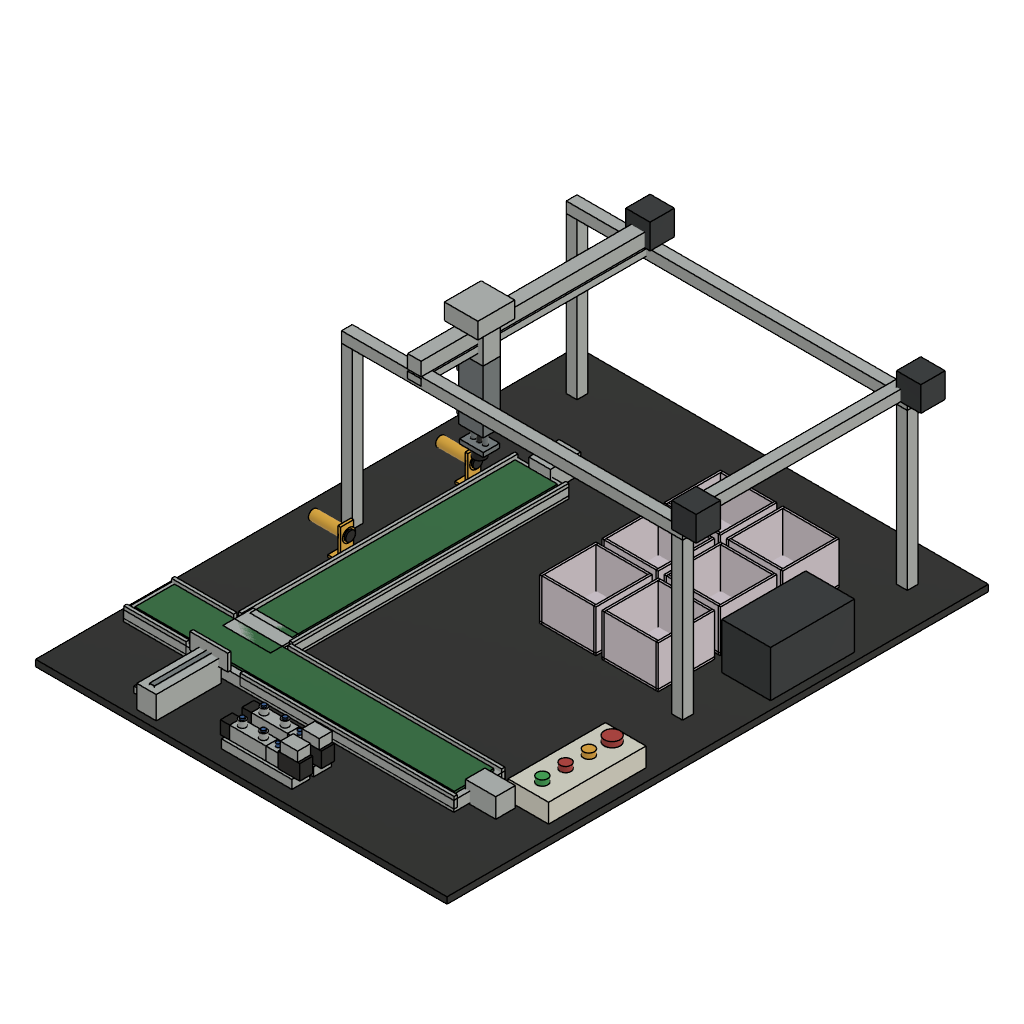
production_twin_v4 (Autodesk Fusion 360 design; units mm, degrees)
Autodesk Fusion 360 part; units mm, degrees
(part 1 of 2)
sketch "base board footprint" plane through (0, 0, 0) normal (0, 0, 1) x (1, 0, 0) in component "base board"
  line L0 (-380, -500) -> (380, -500)
  line L1 (380, -500) -> (380, 500)
  line L2 (380, 500) -> (-380, 500)
  line L3 (-380, 500) -> (-380, -500)
extrude "Extrude1" add sketch "base board footprint" along normal blind 12 makes body 1 in component "base board"
sketch "long conveyor chassis footprint" plane through (0, 0, 0) normal (0, 0, 1) x (1, 0, 0) in component "long conveyor chassis"
  line L0 (-50, -255) -> (50, -255)
  line L1 (50, -255) -> (50, 255)
  line L2 (50, 255) -> (-50, 255)
  line L3 (-50, 255) -> (-50, -255)
extrude "Extrude1'" add sketch "long conveyor chassis footprint" along normal blind 19 separate body makes body 2 in component "long conveyor chassis"
sketch "long green belt footprint" plane through (0, 0, 0) normal (0, 0, 1) x (1, 0, 0) in component "long green belt"
  line L0 (-39, -245) -> (39, -245)
  line L1 (39, -245) -> (39, 245)
  line L2 (39, 245) -> (-39, 245)
  line L3 (-39, 245) -> (-39, -245)
extrude "Extrude1''" add sketch "long green belt footprint" along normal blind 4 separate body makes body 3 in component "long green belt"
sketch "front conveyor chassis footprint" plane through (0, 0, 0) normal (0, 0, 1) x (1, 0, 0) in component "front conveyor chassis"
  line L0 (-305, -47.5) -> (305, -47.5)
  line L1 (305, -47.5) -> (305, 47.5)
  line L2 (305, 47.5) -> (-305, 47.5)
  line L3 (-305, 47.5) -> (-305, -47.5)
extrude "Extrude1'''" add sketch "front conveyor chassis footprint" along normal blind 19 separate body makes body 4 in component "front conveyor chassis"
sketch "front green belt footprint" plane through (0, 0, 0) normal (0, 0, 1) x (1, 0, 0) in component "front green belt"
  line L0 (-295, -36.5) -> (295, -36.5)
  line L1 (295, -36.5) -> (295, 36.5)
  line L2 (295, 36.5) -> (-295, 36.5)
  line L3 (-295, 36.5) -> (-295, -36.5)
extrude "Extrude1''''" add sketch "front green belt footprint" along normal blind 4 separate body makes body 5 in component "front green belt"
sketch "long conveyor side rail -1 footprint" plane through (0, 0, 0) normal (0, 0, 1) x (1, 0, 0) in component "long conveyor side rail -1"
  line L0 (-3, -255) -> (3, -255)
  line L1 (3, -255) -> (3, 255)
  line L2 (3, 255) -> (-3, 255)
  line L3 (-3, 255) -> (-3, -255)
extrude "Extrude1'''''" add sketch "long conveyor side rail -1 footprint" along normal blind 20 separate body makes body 6 in component "long conveyor side rail -1"
sketch "front conveyor side rail -1 left footprint" plane through (0, 0, 0) normal (0, 0, 1) x (1, 0, 0) in component "front conveyor side rail -1 left"
  line L0 (-57.5, -3) -> (57.5, -3)
  line L1 (57.5, -3) -> (57.5, 3)
  line L2 (57.5, 3) -> (-57.5, 3)
  line L3 (-57.5, 3) -> (-57.5, -3)
extrude "Extrude1''''''" add sketch "front conveyor side rail -1 left footprint" along normal blind 20 separate body makes body 7 in component "front conveyor side rail -1 left"
sketch "front conveyor side rail -1 right footprint" plane through (0, 0, 0) normal (0, 0, 1) x (1, 0, 0) in component "front conveyor side rail -1 right"
  line L0 (-197.5, -3) -> (197.5, -3)
  line L1 (197.5, -3) -> (197.5, 3)
  line L2 (197.5, 3) -> (-197.5, 3)
  line L3 (-197.5, 3) -> (-197.5, -3)
extrude "Extrude1'''''''" add sketch "front conveyor side rail -1 right footprint" along normal blind 20 separate body makes body 8 in component "front conveyor side rail -1 right"
sketch "long conveyor side rail 1 footprint" plane through (0, 0, 0) normal (0, 0, 1) x (1, 0, 0) in component "long conveyor side rail 1"
  line L0 (-3, -255) -> (3, -255)
  line L1 (3, -255) -> (3, 255)
  line L2 (3, 255) -> (-3, 255)
  line L3 (-3, 255) -> (-3, -255)
extrude "Extrude1''''''''" add sketch "long conveyor side rail 1 footprint" along normal blind 20 separate body makes body 9 in component "long conveyor side rail 1"
sketch "front conveyor side rail 1 left footprint" plane through (0, 0, 0) normal (0, 0, 1) x (1, 0, 0) in component "front conveyor side rail 1 left"
  line L0 (-57.5, -3) -> (57.5, -3)
  line L1 (57.5, -3) -> (57.5, 3)
  line L2 (57.5, 3) -> (-57.5, 3)
  line L3 (-57.5, 3) -> (-57.5, -3)
extrude "Extrude1'''''''''" add sketch "front conveyor side rail 1 left footprint" along normal blind 20 separate body makes body 10 in component "front conveyor side rail 1 left"
sketch "front conveyor side rail 1 right footprint" plane through (0, 0, 0) normal (0, 0, 1) x (1, 0, 0) in component "front conveyor side rail 1 right"
  line L0 (-197.5, -3) -> (197.5, -3)
  line L1 (197.5, -3) -> (197.5, 3)
  line L2 (197.5, 3) -> (-197.5, 3)
  line L3 (-197.5, 3) -> (-197.5, -3)
extrude "Extrude1''''''''''" add sketch "front conveyor side rail 1 right footprint" along normal blind 20 separate body makes body 11 in component "front conveyor side rail 1 right"
sketch "Sketch1" plane through (0, 0, 0) normal (0, 0, 1) x (1, 0, 0) in component "front conveyor roller -330"
  circle A0 centre (0, 0) radius 12
extrude "Extrude1'''''''''''" add sketch "Sketch1" along normal blind 75 separate body makes body 12 in component "front conveyor roller -330"
sketch "Sketch1 (2)" plane through (0, 0, 0) normal (0, 0, 1) x (1, 0, 0) in component "front conveyor roller 250"
  circle A0 centre (0, 0) radius 12
extrude "Extrude1''''''''''''" add sketch "Sketch1 (2)" along normal blind 75 separate body makes body 13 in component "front conveyor roller 250"
sketch "Sketch1 (3)" plane through (0, 0, 0) normal (0, 0, 1) x (1, 0, 0) in component "long conveyor roller -265"
  circle A0 centre (0, 0) radius 12
extrude "Extrude1'''''''''''''" add sketch "Sketch1 (3)" along normal blind 78 separate body makes body 14 in component "long conveyor roller -265"
sketch "Sketch1 (4)" plane through (0, 0, 0) normal (0, 0, 1) x (1, 0, 0) in component "long conveyor roller 225"
  circle A0 centre (0, 0) radius 12
extrude "Extrude1''''''''''''''" add sketch "Sketch1 (4)" along normal blind 78 separate body makes body 15 in component "long conveyor roller 225"
sketch "front conveyor DC motor footprint" plane through (0, 0, 0) normal (0, 0, 1) x (1, 0, 0) in component "front conveyor DC motor"
  line L0 (-28, -18) -> (28, -18)
  line L1 (28, -18) -> (28, 18)
  line L2 (28, 18) -> (-28, 18)
  line L3 (-28, 18) -> (-28, -18)
extrude "Extrude1'''''''''''''''" add sketch "front conveyor DC motor footprint" along normal blind 36 separate body makes body 16 in component "front conveyor DC motor"
sketch "long conveyor DC motor footprint" plane through (0, 0, 0) normal (0, 0, 1) x (1, 0, 0) in component "long conveyor DC motor"
  line L0 (-20, -28) -> (20, -28)
  line L1 (20, -28) -> (20, 28)
  line L2 (20, 28) -> (-20, 28)
  line L3 (-20, 28) -> (-20, -28)
extrude "Extrude1''''''''''''''''" add sketch "long conveyor DC motor footprint" along normal blind 36 separate body makes body 17 in component "long conveyor DC motor"
sketch "L transfer guide footprint" plane through (0, 0, 0) normal (0, 0, 1) x (1, 0, 0) in component "L transfer guide"
  line L0 (-44, -28) -> (44, -28)
  line L1 (44, -28) -> (44, 28)
  line L2 (44, 28) -> (-44, 28)
  line L3 (-44, 28) -> (-44, -28)
extrude "Extrude1'''''''''''''''''" add sketch "L transfer guide footprint" along normal blind 4 separate body makes body 18 in component "L transfer guide"
sketch "gantry post left front footprint" plane through (0, 0, 0) normal (0, 0, 1) x (1, 0, 0) in component "gantry post left front"
  line L0 (-10, -10) -> (10, -10)
  line L1 (10, -10) -> (10, 10)
  line L2 (10, 10) -> (-10, 10)
  line L3 (-10, 10) -> (-10, -10)
extrude "Extrude1''''''''''''''''''" add sketch "gantry post left front footprint" along normal blind 288 separate body makes body 19 in component "gantry post left front"
sketch "gantry post left rear footprint" plane through (0, 0, 0) normal (0, 0, 1) x (1, 0, 0) in component "gantry post left rear"
  line L0 (-10, -10) -> (10, -10)
  line L1 (10, -10) -> (10, 10)
  line L2 (10, 10) -> (-10, 10)
  line L3 (-10, 10) -> (-10, -10)
extrude "Extrude1'''''''''''''''''''" add sketch "gantry post left rear footprint" along normal blind 288 separate body makes body 20 in component "gantry post left rear"
sketch "gantry post right front footprint" plane through (0, 0, 0) normal (0, 0, 1) x (1, 0, 0) in component "gantry post right front"
  line L0 (-10, -10) -> (10, -10)
  line L1 (10, -10) -> (10, 10)
  line L2 (10, 10) -> (-10, 10)
  line L3 (-10, 10) -> (-10, -10)
extrude "Extrude1''''''''''''''''''''" add sketch "gantry post right front footprint" along normal blind 288 separate body makes body 21 in component "gantry post right front"
sketch "gantry post right rear footprint" plane through (0, 0, 0) normal (0, 0, 1) x (1, 0, 0) in component "gantry post right rear"
  line L0 (-10, -10) -> (10, -10)
  line L1 (10, -10) -> (10, 10)
  line L2 (10, 10) -> (-10, 10)
  line L3 (-10, 10) -> (-10, -10)
extrude "Extrude1'''''''''''''''''''''" add sketch "gantry post right rear footprint" along normal blind 288 separate body makes body 22 in component "gantry post right rear"
sketch "gantry X rail front footprint" plane through (0, 0, 0) normal (0, 0, 1) x (1, 0, 0) in component "gantry X rail front"
  line L0 (-315, -10) -> (315, -10)
  line L1 (315, -10) -> (315, 10)
  line L2 (315, 10) -> (-315, 10)
  line L3 (-315, 10) -> (-315, -10)
extrude "Extrude1''''''''''''''''''''''" add sketch "gantry X rail front footprint" along normal blind 20 separate body makes body 23 in component "gantry X rail front"
sketch "gantry X rail rear footprint" plane through (0, 0, 0) normal (0, 0, 1) x (1, 0, 0) in component "gantry X rail rear"
  line L0 (-315, -10) -> (315, -10)
  line L1 (315, -10) -> (315, 10)
  line L2 (315, 10) -> (-315, 10)
  line L3 (-315, 10) -> (-315, -10)
extrude "Extrude1'''''''''''''''''''''''" add sketch "gantry X rail rear footprint" along normal blind 20 separate body makes body 24 in component "gantry X rail rear"
sketch "right Y guide footprint" plane through (0, 0, 0) normal (0, 0, 1) x (1, 0, 0) in component "right Y guide"
  line L0 (-10, -217.5) -> (10, -217.5)
  line L1 (10, -217.5) -> (10, 217.5)
  line L2 (10, 217.5) -> (-10, 217.5)
  line L3 (-10, 217.5) -> (-10, -217.5)
extrude "Extrude1''''''''''''''''''''''''" add sketch "right Y guide footprint" along normal blind 20 separate body makes body 25 in component "right Y guide"
sketch "moving Y rail footprint" plane through (0, 0, 0) normal (0, 0, 1) x (1, 0, 0) in component "moving Y rail"
  line L0 (-12.5, -217.5) -> (12.5, -217.5)
  line L1 (12.5, -217.5) -> (12.5, 217.5)
  line L2 (12.5, 217.5) -> (-12.5, 217.5)
  line L3 (-12.5, 217.5) -> (-12.5, -217.5)
extrude "Extrude1'''''''''''''''''''''''''" add sketch "moving Y rail footprint" along normal blind 25 separate body makes body 26 in component "moving Y rail"
sketch "pick carriage footprint" plane through (0, 0, 0) normal (0, 0, 1) x (1, 0, 0) in component "pick carriage"
  line L0 (-31, -34) -> (31, -34)
  line L1 (31, -34) -> (31, 34)
  line L2 (31, 34) -> (-31, 34)
  line L3 (-31, 34) -> (-31, -34)
extrude "Extrude1''''''''''''''''''''''''''" add sketch "pick carriage footprint" along normal blind 30 separate body makes body 27 in component "pick carriage"
sketch "moving Y rail lower guide footprint" plane through (0, 0, 0) normal (0, 0, 1) x (1, 0, 0) in component "moving Y rail lower guide"
  line L0 (-12.5, -217.5) -> (12.5, -217.5)
  line L1 (12.5, -217.5) -> (12.5, 217.5)
  line L2 (12.5, 217.5) -> (-12.5, 217.5)
  line L3 (-12.5, 217.5) -> (-12.5, -217.5)
extrude "Extrude1'''''''''''''''''''''''''''" add sketch "moving Y rail lower guide footprint" along normal blind 12 separate body makes body 28 in component "moving Y rail lower guide"
sketch "A2 carriage mount footprint" plane through (0, 0, 0) normal (0, 0, 1) x (1, 0, 0) in component "A2 carriage mount"
  line L0 (-22.5, -16) -> (22.5, -16)
  line L1 (22.5, -16) -> (22.5, 16)
  line L2 (22.5, 16) -> (-22.5, 16)
  line L3 (-22.5, 16) -> (-22.5, -16)
extrude "Extrude1''''''''''''''''''''''''''''" add sketch "A2 carriage mount footprint" along normal blind 55 separate body makes body 29 in component "A2 carriage mount"
sketch "A2 TN10X75-S twin rod body footprint" plane through (0, 0, 0) normal (0, 0, 1) x (1, 0, 0) in component "A2 TN10X75-S twin rod body"
  line L0 (-22.5, -16) -> (22.5, -16)
  line L1 (22.5, -16) -> (22.5, 16)
  line L2 (22.5, 16) -> (-22.5, 16)
  line L3 (-22.5, 16) -> (-22.5, -16)
extrude "Extrude1'''''''''''''''''''''''''''''" add sketch "A2 TN10X75-S twin rod body footprint" along normal blind 115 separate body makes body 30 in component "A2 TN10X75-S twin rod body"
sketch "Sketch1 (5)" plane through (0, 0, 0) normal (0, 0, 1) x (1, 0, 0) in component "A2 rod at x -191"
  circle A0 centre (0, 0) radius 4
extrude "Extrude1''''''''''''''''''''''''''''''" add sketch "Sketch1 (5)" along normal blind 99 separate body makes body 31 in component "A2 rod at x -191"
sketch "Sketch1 (6)" plane through (0, 0, 0) normal (0, 0, 1) x (1, 0, 0) in component "A2 rod at x -169"
  circle A0 centre (0, 0) radius 4
extrude "Extrude1'''''''''''''''''''''''''''''''" add sketch "Sketch1 (6)" along normal blind 99 separate body makes body 32 in component "A2 rod at x -169"
sketch "A2 rod end plate footprint" plane through (0, 0, 0) normal (0, 0, 1) x (1, 0, 0) in component "A2 rod end plate"
  line L0 (-22, -15) -> (22, -15)
  line L1 (22, -15) -> (22, 15)
  line L2 (22, 15) -> (-22, 15)
  line L3 (-22, 15) -> (-22, -15)
extrude "Extrude1''''''''''''''''''''''''''''''''" add sketch "A2 rod end plate footprint" along normal blind 8 separate body makes body 33 in component "A2 rod end plate"
sketch "Sketch1 (7)" plane through (0, 0, 0) normal (0, 0, 1) x (1, 0, 0) in component "vacuum cup"
  circle A0 centre (0, 0) radius 11
extrude "Extrude1'''''''''''''''''''''''''''''''''" add sketch "Sketch1 (7)" along normal blind 16 separate body makes body 34 in component "vacuum cup"
sketch "Sketch1 (8)" plane through (0, 0, 0) normal (0, 0, 1) x (1, 0, 0) in component "vacuum cup stem"
  circle A0 centre (0, 0) radius 4
extrude "Extrude1''''''''''''''''''''''''''''''''''" add sketch "Sketch1 (8)" along normal blind 16 separate body makes body 35 in component "vacuum cup stem"
sketch "S3 A2 upper proximity switch (code pending) footprint" plane through (0, 0, 0) normal (0, 0, 1) x (1, 0, 0) in component "S3 A2 upper proximity switch (code pending)"
  line L0 (-4, -11) -> (4, -11)
  line L1 (4, -11) -> (4, 11)
  line L2 (4, 11) -> (-4, 11)
  line L3 (-4, 11) -> (-4, -11)
extrude "Extrude1'''''''''''''''''''''''''''''''''''" add sketch "S3 A2 upper proximity switch (code pending) footprint" along normal blind 13 separate body makes body 36 in component "S3 A2 upper proximity switch (code pending)"
sketch "S4 A2 lower proximity switch (code pending) footprint" plane through (0, 0, 0) normal (0, 0, 1) x (1, 0, 0) in component "S4 A2 lower proximity switch (code pending)"
  line L0 (-4, -11) -> (4, -11)
  line L1 (4, -11) -> (4, 11)
  line L2 (4, 11) -> (-4, 11)
  line L3 (-4, 11) -> (-4, -11)
extrude "Extrude1''''''''''''''''''''''''''''''''''''" add sketch "S4 A2 lower proximity switch (code pending) footprint" along normal blind 13 separate body makes body 37 in component "S4 A2 lower proximity switch (code pending)"
sketch "motor Y carriage footprint" plane through (0, 0, 0) normal (0, 0, 1) x (1, 0, 0) in component "motor Y carriage"
  line L0 (-22.5, -22.5) -> (22.5, -22.5)
  line L1 (22.5, -22.5) -> (22.5, 22.5)
  line L2 (22.5, 22.5) -> (-22.5, 22.5)
  line L3 (-22.5, 22.5) -> (-22.5, -22.5)
extrude "Extrude1'''''''''''''''''''''''''''''''''''''" add sketch "motor Y carriage footprint" along normal blind 46 separate body makes body 38 in component "motor Y carriage"
sketch "motor X rear footprint" plane through (0, 0, 0) normal (0, 0, 1) x (1, 0, 0) in component "motor X rear"
  line L0 (-22.5, -22.5) -> (22.5, -22.5)
  line L1 (22.5, -22.5) -> (22.5, 22.5)
  line L2 (22.5, 22.5) -> (-22.5, 22.5)
  line L3 (-22.5, 22.5) -> (-22.5, -22.5)
extrude "Extrude1''''''''''''''''''''''''''''''''''''''" add sketch "motor X rear footprint" along normal blind 46 separate body makes body 39 in component "motor X rear"
sketch "motor X front footprint" plane through (0, 0, 0) normal (0, 0, 1) x (1, 0, 0) in component "motor X front"
  line L0 (-22.5, -22.5) -> (22.5, -22.5)
  line L1 (22.5, -22.5) -> (22.5, 22.5)
  line L2 (22.5, 22.5) -> (-22.5, 22.5)
  line L3 (-22.5, 22.5) -> (-22.5, -22.5)
extrude "Extrude1'''''''''''''''''''''''''''''''''''''''" add sketch "motor X front footprint" along normal blind 46 separate body makes body 40 in component "motor X front"
sketch "bin R1C1 floor footprint" plane through (0, 0, 0) normal (0, 0, 1) x (1, 0, 0) in component "bin R1C1"
  line L0 (-52, -52) -> (52, -52)
  line L1 (52, -52) -> (52, 52)
  line L2 (52, 52) -> (-52, 52)
  line L3 (-52, 52) -> (-52, -52)
extrude "Extrude1''''''''''''''''''''''''''''''''''''''''" add sketch "bin R1C1 floor footprint" along normal blind 4 separate body makes body 41 in component "bin R1C1"
sketch "bin R1C1 side wall -1 footprint" plane through (0, 0, 0) normal (0, 0, 1) x (1, 0, 0) in component "bin R1C1"
  line L0 (-52, -52) -> (-48, -52)
  line L1 (-48, -52) -> (-48, 52)
  line L2 (-48, 52) -> (-52, 52)
  line L3 (-52, 52) -> (-52, -52)
extrude "Extrude2" add sketch "bin R1C1 side wall -1 footprint" along normal blind 78 separate body makes body 42 in component "bin R1C1"
sketch "bin R1C1 end wall -1 footprint" plane through (0, 0, 0) normal (0, 0, 1) x (1, 0, 0) in component "bin R1C1"
  line L0 (-48, -52) -> (48, -52)
  line L1 (48, -52) -> (48, -48)
  line L2 (48, -48) -> (-48, -48)
  line L3 (-48, -48) -> (-48, -52)
extrude "Extrude3" add sketch "bin R1C1 end wall -1 footprint" along normal blind 78 separate body makes body 43 in component "bin R1C1"
sketch "bin R1C1 side wall 1 footprint" plane through (0, 0, 0) normal (0, 0, 1) x (1, 0, 0) in component "bin R1C1"
  line L0 (48, -52) -> (52, -52)
  line L1 (52, -52) -> (52, 52)
  line L2 (52, 52) -> (48, 52)
  line L3 (48, 52) -> (48, -52)
extrude "Extrude4" add sketch "bin R1C1 side wall 1 footprint" along normal blind 78 separate body makes body 44 in component "bin R1C1"
sketch "bin R1C1 end wall 1 footprint" plane through (0, 0, 0) normal (0, 0, 1) x (1, 0, 0) in component "bin R1C1"
  line L0 (-48, 48) -> (48, 48)
  line L1 (48, 48) -> (48, 52)
  line L2 (48, 52) -> (-48, 52)
  line L3 (-48, 52) -> (-48, 48)
extrude "Extrude5" add sketch "bin R1C1 end wall 1 footprint" along normal blind 78 separate body makes body 45 in component "bin R1C1"
sketch "bin R1C2 floor footprint" plane through (0, 0, 0) normal (0, 0, 1) x (1, 0, 0) in component "bin R1C2"
  line L0 (-52, -52) -> (52, -52)
  line L1 (52, -52) -> (52, 52)
  line L2 (52, 52) -> (-52, 52)
  line L3 (-52, 52) -> (-52, -52)
extrude "Extrude1'''''''''''''''''''''''''''''''''''''''''" add sketch "bin R1C2 floor footprint" along normal blind 4 separate body makes body 46 in component "bin R1C2"
sketch "bin R1C2 side wall -1 footprint" plane through (0, 0, 0) normal (0, 0, 1) x (1, 0, 0) in component "bin R1C2"
  line L0 (-52, -52) -> (-48, -52)
  line L1 (-48, -52) -> (-48, 52)
  line L2 (-48, 52) -> (-52, 52)
  line L3 (-52, 52) -> (-52, -52)
extrude "Extrude2'" add sketch "bin R1C2 side wall -1 footprint" along normal blind 78 separate body makes body 47 in component "bin R1C2"
sketch "bin R1C2 end wall -1 footprint" plane through (0, 0, 0) normal (0, 0, 1) x (1, 0, 0) in component "bin R1C2"
  line L0 (-48, -52) -> (48, -52)
  line L1 (48, -52) -> (48, -48)
  line L2 (48, -48) -> (-48, -48)
  line L3 (-48, -48) -> (-48, -52)
extrude "Extrude3'" add sketch "bin R1C2 end wall -1 footprint" along normal blind 78 separate body makes body 48 in component "bin R1C2"
sketch "bin R1C2 side wall 1 footprint" plane through (0, 0, 0) normal (0, 0, 1) x (1, 0, 0) in component "bin R1C2"
  line L0 (48, -52) -> (52, -52)
  line L1 (52, -52) -> (52, 52)
  line L2 (52, 52) -> (48, 52)
  line L3 (48, 52) -> (48, -52)
extrude "Extrude4'" add sketch "bin R1C2 side wall 1 footprint" along normal blind 78 separate body makes body 49 in component "bin R1C2"
sketch "bin R1C2 end wall 1 footprint" plane through (0, 0, 0) normal (0, 0, 1) x (1, 0, 0) in component "bin R1C2"
  line L0 (-48, 48) -> (48, 48)
  line L1 (48, 48) -> (48, 52)
  line L2 (48, 52) -> (-48, 52)
  line L3 (-48, 52) -> (-48, 48)
extrude "Extrude5'" add sketch "bin R1C2 end wall 1 footprint" along normal blind 78 separate body makes body 50 in component "bin R1C2"
sketch "bin R2C1 floor footprint" plane through (0, 0, 0) normal (0, 0, 1) x (1, 0, 0) in component "bin R2C1"
  line L0 (-52, -52) -> (52, -52)
  line L1 (52, -52) -> (52, 52)
  line L2 (52, 52) -> (-52, 52)
  line L3 (-52, 52) -> (-52, -52)
extrude "Extrude1''''''''''''''''''''''''''''''''''''''''''" add sketch "bin R2C1 floor footprint" along normal blind 4 separate body makes body 51 in component "bin R2C1"
sketch "bin R2C1 side wall -1 footprint" plane through (0, 0, 0) normal (0, 0, 1) x (1, 0, 0) in component "bin R2C1"
  line L0 (-52, -52) -> (-48, -52)
  line L1 (-48, -52) -> (-48, 52)
  line L2 (-48, 52) -> (-52, 52)
  line L3 (-52, 52) -> (-52, -52)
extrude "Extrude2''" add sketch "bin R2C1 side wall -1 footprint" along normal blind 78 separate body makes body 52 in component "bin R2C1"
sketch "bin R2C1 end wall -1 footprint" plane through (0, 0, 0) normal (0, 0, 1) x (1, 0, 0) in component "bin R2C1"
  line L0 (-48, -52) -> (48, -52)
  line L1 (48, -52) -> (48, -48)
  line L2 (48, -48) -> (-48, -48)
  line L3 (-48, -48) -> (-48, -52)
extrude "Extrude3''" add sketch "bin R2C1 end wall -1 footprint" along normal blind 78 separate body makes body 53 in component "bin R2C1"
sketch "bin R2C1 side wall 1 footprint" plane through (0, 0, 0) normal (0, 0, 1) x (1, 0, 0) in component "bin R2C1"
  line L0 (48, -52) -> (52, -52)
  line L1 (52, -52) -> (52, 52)
  line L2 (52, 52) -> (48, 52)
  line L3 (48, 52) -> (48, -52)
extrude "Extrude4''" add sketch "bin R2C1 side wall 1 footprint" along normal blind 78 separate body makes body 54 in component "bin R2C1"
sketch "bin R2C1 end wall 1 footprint" plane through (0, 0, 0) normal (0, 0, 1) x (1, 0, 0) in component "bin R2C1"
  line L0 (-48, 48) -> (48, 48)
  line L1 (48, 48) -> (48, 52)
  line L2 (48, 52) -> (-48, 52)
  line L3 (-48, 52) -> (-48, 48)
extrude "Extrude5''" add sketch "bin R2C1 end wall 1 footprint" along normal blind 78 separate body makes body 55 in component "bin R2C1"
sketch "bin R2C2 floor footprint" plane through (0, 0, 0) normal (0, 0, 1) x (1, 0, 0) in component "bin R2C2"
  line L0 (-52, -52) -> (52, -52)
  line L1 (52, -52) -> (52, 52)
  line L2 (52, 52) -> (-52, 52)
  line L3 (-52, 52) -> (-52, -52)
extrude "Extrude1'''''''''''''''''''''''''''''''''''''''''''" add sketch "bin R2C2 floor footprint" along normal blind 4 separate body makes body 56 in component "bin R2C2"
sketch "bin R2C2 side wall -1 footprint" plane through (0, 0, 0) normal (0, 0, 1) x (1, 0, 0) in component "bin R2C2"
  line L0 (-52, -52) -> (-48, -52)
  line L1 (-48, -52) -> (-48, 52)
  line L2 (-48, 52) -> (-52, 52)
  line L3 (-52, 52) -> (-52, -52)
extrude "Extrude2'''" add sketch "bin R2C2 side wall -1 footprint" along normal blind 78 separate body makes body 57 in component "bin R2C2"
sketch "bin R2C2 end wall -1 footprint" plane through (0, 0, 0) normal (0, 0, 1) x (1, 0, 0) in component "bin R2C2"
  line L0 (-48, -52) -> (48, -52)
  line L1 (48, -52) -> (48, -48)
  line L2 (48, -48) -> (-48, -48)
  line L3 (-48, -48) -> (-48, -52)
extrude "Extrude3'''" add sketch "bin R2C2 end wall -1 footprint" along normal blind 78 separate body makes body 58 in component "bin R2C2"
sketch "bin R2C2 side wall 1 footprint" plane through (0, 0, 0) normal (0, 0, 1) x (1, 0, 0) in component "bin R2C2"
  line L0 (48, -52) -> (52, -52)
  line L1 (52, -52) -> (52, 52)
  line L2 (52, 52) -> (48, 52)
  line L3 (48, 52) -> (48, -52)
extrude "Extrude4'''" add sketch "bin R2C2 side wall 1 footprint" along normal blind 78 separate body makes body 59 in component "bin R2C2"
sketch "bin R2C2 end wall 1 footprint" plane through (0, 0, 0) normal (0, 0, 1) x (1, 0, 0) in component "bin R2C2"
  line L0 (-48, 48) -> (48, 48)
  line L1 (48, 48) -> (48, 52)
  line L2 (48, 52) -> (-48, 52)
  line L3 (-48, 52) -> (-48, 48)
extrude "Extrude5'''" add sketch "bin R2C2 end wall 1 footprint" along normal blind 78 separate body makes body 60 in component "bin R2C2"
sketch "bin R3C1 floor footprint" plane through (0, 0, 0) normal (0, 0, 1) x (1, 0, 0) in component "bin R3C1"
  line L0 (-52, -52) -> (52, -52)
  line L1 (52, -52) -> (52, 52)
  line L2 (52, 52) -> (-52, 52)
  line L3 (-52, 52) -> (-52, -52)
extrude "Extrude1''''''''''''''''''''''''''''''''''''''''''''" add sketch "bin R3C1 floor footprint" along normal blind 4 separate body makes body 61 in component "bin R3C1"
sketch "bin R3C1 side wall -1 footprint" plane through (0, 0, 0) normal (0, 0, 1) x (1, 0, 0) in component "bin R3C1"
  line L0 (-52, -52) -> (-48, -52)
  line L1 (-48, -52) -> (-48, 52)
  line L2 (-48, 52) -> (-52, 52)
  line L3 (-52, 52) -> (-52, -52)
extrude "Extrude2''''" add sketch "bin R3C1 side wall -1 footprint" along normal blind 78 separate body makes body 62 in component "bin R3C1"
sketch "bin R3C1 end wall -1 footprint" plane through (0, 0, 0) normal (0, 0, 1) x (1, 0, 0) in component "bin R3C1"
  line L0 (-48, -52) -> (48, -52)
  line L1 (48, -52) -> (48, -48)
  line L2 (48, -48) -> (-48, -48)
  line L3 (-48, -48) -> (-48, -52)
extrude "Extrude3''''" add sketch "bin R3C1 end wall -1 footprint" along normal blind 78 separate body makes body 63 in component "bin R3C1"
sketch "bin R3C1 side wall 1 footprint" plane through (0, 0, 0) normal (0, 0, 1) x (1, 0, 0) in component "bin R3C1"
  line L0 (48, -52) -> (52, -52)
  line L1 (52, -52) -> (52, 52)
  line L2 (52, 52) -> (48, 52)
  line L3 (48, 52) -> (48, -52)
extrude "Extrude4''''" add sketch "bin R3C1 side wall 1 footprint" along normal blind 78 separate body makes body 64 in component "bin R3C1"
sketch "bin R3C1 end wall 1 footprint" plane through (0, 0, 0) normal (0, 0, 1) x (1, 0, 0) in component "bin R3C1"
  line L0 (-48, 48) -> (48, 48)
  line L1 (48, 48) -> (48, 52)
  line L2 (48, 52) -> (-48, 52)
  line L3 (-48, 52) -> (-48, 48)
extrude "Extrude5''''" add sketch "bin R3C1 end wall 1 footprint" along normal blind 78 separate body makes body 65 in component "bin R3C1"
sketch "bin R3C2 floor footprint" plane through (0, 0, 0) normal (0, 0, 1) x (1, 0, 0) in component "bin R3C2"
  line L0 (-52, -52) -> (52, -52)
  line L1 (52, -52) -> (52, 52)
  line L2 (52, 52) -> (-52, 52)
  line L3 (-52, 52) -> (-52, -52)
extrude "Extrude1'''''''''''''''''''''''''''''''''''''''''''''" add sketch "bin R3C2 floor footprint" along normal blind 4 separate body makes body 66 in component "bin R3C2"
sketch "bin R3C2 side wall -1 footprint" plane through (0, 0, 0) normal (0, 0, 1) x (1, 0, 0) in component "bin R3C2"
  line L0 (-52, -52) -> (-48, -52)
  line L1 (-48, -52) -> (-48, 52)
  line L2 (-48, 52) -> (-52, 52)
  line L3 (-52, 52) -> (-52, -52)
extrude "Extrude2'''''" add sketch "bin R3C2 side wall -1 footprint" along normal blind 78 separate body makes body 67 in component "bin R3C2"
sketch "bin R3C2 end wall -1 footprint" plane through (0, 0, 0) normal (0, 0, 1) x (1, 0, 0) in component "bin R3C2"
  line L0 (-48, -52) -> (48, -52)
  line L1 (48, -52) -> (48, -48)
  line L2 (48, -48) -> (-48, -48)
  line L3 (-48, -48) -> (-48, -52)
extrude "Extrude3'''''" add sketch "bin R3C2 end wall -1 footprint" along normal blind 78 separate body makes body 68 in component "bin R3C2"
sketch "bin R3C2 side wall 1 footprint" plane through (0, 0, 0) normal (0, 0, 1) x (1, 0, 0) in component "bin R3C2"
  line L0 (48, -52) -> (52, -52)
  line L1 (52, -52) -> (52, 52)
  line L2 (52, 52) -> (48, 52)
  line L3 (48, 52) -> (48, -52)
extrude "Extrude4'''''" add sketch "bin R3C2 side wall 1 footprint" along normal blind 78 separate body makes body 69 in component "bin R3C2"
sketch "bin R3C2 end wall 1 footprint" plane through (0, 0, 0) normal (0, 0, 1) x (1, 0, 0) in component "bin R3C2"
  line L0 (-48, 48) -> (48, 48)
  line L1 (48, 48) -> (48, 52)
  line L2 (48, 52) -> (-48, 52)
  line L3 (-48, 52) -> (-48, 48)
extrude "Extrude5'''''" add sketch "bin R3C2 end wall 1 footprint" along normal blind 78 separate body makes body 70 in component "bin R3C2"
sketch "PS1 bracket foot footprint" plane through (0, 0, 0) normal (0, 0, 1) x (1, 0, 0) in component "PS1 bracket foot"
  line L0 (-17.5, -12) -> (17.5, -12)
  line L1 (17.5, -12) -> (17.5, 12)
  line L2 (17.5, 12) -> (-17.5, 12)
  line L3 (-17.5, 12) -> (-17.5, -12)
extrude "Extrude1''''''''''''''''''''''''''''''''''''''''''''''" add sketch "PS1 bracket foot footprint" along normal blind 4 separate body makes body 71 in component "PS1 bracket foot"
sketch "PS1 bracket upright footprint" plane through (0, 0, 0) normal (0, 0, 1) x (1, 0, 0) in component "PS1 bracket upright"
  line L0 (-2.5, -12) -> (2.5, -12)
  line L1 (2.5, -12) -> (2.5, 12)
  line L2 (2.5, 12) -> (-2.5, 12)
  line L3 (-2.5, 12) -> (-2.5, -12)
extrude "Extrude1'''''''''''''''''''''''''''''''''''''''''''''''" add sketch "PS1 bracket upright footprint" along normal blind 56 separate body makes body 72 in component "PS1 bracket upright"
sketch "Sketch1 (9)" plane through (0, 0, 0) normal (0, 0, 1) x (1, 0, 0) in component "PS1 YF-KJ E3F-DS30C4 M18 body"
  circle A0 centre (0, 0) radius 9
extrude "Extrude1''''''''''''''''''''''''''''''''''''''''''''''''" add sketch "Sketch1 (9)" along normal blind 58 separate body makes body 73 in component "PS1 YF-KJ E3F-DS30C4 M18 body"
sketch "Sketch1 (10)" plane through (0, 0, 0) normal (0, 0, 1) x (1, 0, 0) in component "PS1 locking ring"
  circle A0 centre (0, 0) radius 12
extrude "Extrude1'''''''''''''''''''''''''''''''''''''''''''''''''" add sketch "Sketch1 (10)" along normal blind 8 separate body makes body 74 in component "PS1 locking ring"
sketch "Sketch1 (11)" plane through (0, 0, 0) normal (0, 0, 1) x (1, 0, 0) in component "PS1 optical face"
  circle A0 centre (0, 0) radius 9
extrude "Extrude1''''''''''''''''''''''''''''''''''''''''''''''''''" add sketch "Sketch1 (11)" along normal blind 3 separate body makes body 75 in component "PS1 optical face"
sketch "PS2 bracket foot footprint" plane through (0, 0, 0) normal (0, 0, 1) x (1, 0, 0) in component "PS2 bracket foot"
  line L0 (-17.5, -12) -> (17.5, -12)
  line L1 (17.5, -12) -> (17.5, 12)
  line L2 (17.5, 12) -> (-17.5, 12)
  line L3 (-17.5, 12) -> (-17.5, -12)
extrude "Extrude1'''''''''''''''''''''''''''''''''''''''''''''''''''" add sketch "PS2 bracket foot footprint" along normal blind 4 separate body makes body 76 in component "PS2 bracket foot"
sketch "PS2 bracket upright footprint" plane through (0, 0, 0) normal (0, 0, 1) x (1, 0, 0) in component "PS2 bracket upright"
  line L0 (-2.5, -12) -> (2.5, -12)
  line L1 (2.5, -12) -> (2.5, 12)
  line L2 (2.5, 12) -> (-2.5, 12)
  line L3 (-2.5, 12) -> (-2.5, -12)
extrude "Extrude1''''''''''''''''''''''''''''''''''''''''''''''''''''" add sketch "PS2 bracket upright footprint" along normal blind 56 separate body makes body 77 in component "PS2 bracket upright"
sketch "Sketch1 (12)" plane through (0, 0, 0) normal (0, 0, 1) x (1, 0, 0) in component "PS2 YF-KJ E3F-DS30C4 M18 body"
  circle A0 centre (0, 0) radius 9
extrude "Extrude1'''''''''''''''''''''''''''''''''''''''''''''''''''''" add sketch "Sketch1 (12)" along normal blind 58 separate body makes body 78 in component "PS2 YF-KJ E3F-DS30C4 M18 body"
sketch "Sketch1 (13)" plane through (0, 0, 0) normal (0, 0, 1) x (1, 0, 0) in component "PS2 locking ring"
  circle A0 centre (0, 0) radius 12
extrude "Extrude1''''''''''''''''''''''''''''''''''''''''''''''''''''''" add sketch "Sketch1 (13)" along normal blind 8 separate body makes body 79 in component "PS2 locking ring"
sketch "Sketch1 (14)" plane through (0, 0, 0) normal (0, 0, 1) x (1, 0, 0) in component "PS2 optical face"
  circle A0 centre (0, 0) radius 9
extrude "Extrude1'''''''''''''''''''''''''''''''''''''''''''''''''''''''" add sketch "Sketch1 (14)" along normal blind 3 separate body makes body 80 in component "PS2 optical face"
sketch "A1 front pusher cylinder footprint" plane through (0, 0, 0) normal (0, 0, 1) x (1, 0, 0) in component "A1 front pusher cylinder"
  line L0 (-18, -60) -> (18, -60)
  line L1 (18, -60) -> (18, 60)
  line L2 (18, 60) -> (-18, 60)
  line L3 (-18, 60) -> (-18, -60)
extrude "Extrude1''''''''''''''''''''''''''''''''''''''''''''''''''''''''" add sketch "A1 front pusher cylinder footprint" along normal blind 42 separate body makes body 81 in component "A1 front pusher cylinder"
sketch "A1 pusher rod footprint" plane through (0, 0, 0) normal (0, 0, 1) x (1, 0, 0) in component "A1 pusher rod"
  line L0 (-4.5, -54) -> (4.5, -54)
  line L1 (4.5, -54) -> (4.5, 54)
  line L2 (4.5, 54) -> (-4.5, 54)
  line L3 (-4.5, 54) -> (-4.5, -54)
extrude "Extrude1'''''''''''''''''''''''''''''''''''''''''''''''''''''''''" add sketch "A1 pusher rod footprint" along normal blind 9 separate body makes body 82 in component "A1 pusher rod"
sketch "A1 pusher plate footprint" plane through (0, 0, 0) normal (0, 0, 1) x (1, 0, 0) in component "A1 pusher plate"
  line L0 (-35, -3) -> (35, -3)
  line L1 (35, -3) -> (35, 3)
  line L2 (35, 3) -> (-35, 3)
  line L3 (-35, 3) -> (-35, -3)
extrude "Extrude1''''''''''''''''''''''''''''''''''''''''''''''''''''''''''" add sketch "A1 pusher plate footprint" along normal blind 30 separate body makes body 83 in component "A1 pusher plate"
sketch "S1 A1 retracted switch (code pending) footprint" plane through (0, 0, 0) normal (0, 0, 1) x (1, 0, 0) in component "S1 A1 retracted switch (code pending)"
  line L0 (-4.5, -8) -> (4.5, -8)
  line L1 (4.5, -8) -> (4.5, 8)
  line L2 (4.5, 8) -> (-4.5, 8)
  line L3 (-4.5, 8) -> (-4.5, -8)
extrude "Extrude1'''''''''''''''''''''''''''''''''''''''''''''''''''''''''''" add sketch "S1 A1 retracted switch (code pending) footprint" along normal blind 11 separate body makes body 84 in component "S1 A1 retracted switch (code pending)"
sketch "S2 A1 extended switch (code pending) footprint" plane through (0, 0, 0) normal (0, 0, 1) x (1, 0, 0) in component "S2 A1 extended switch (code pending)"
  line L0 (-4.5, -8) -> (4.5, -8)
  line L1 (4.5, -8) -> (4.5, 8)
  line L2 (4.5, 8) -> (-4.5, 8)
  line L3 (-4.5, 8) -> (-4.5, -8)
extrude "Extrude1''''''''''''''''''''''''''''''''''''''''''''''''''''''''''''" add sketch "S2 A1 extended switch (code pending) footprint" along normal blind 11 separate body makes body 85 in component "S2 A1 extended switch (code pending)"
sketch "Y1 4V210-08 manifold footprint" plane through (0, 0, 0) normal (0, 0, 1) x (1, 0, 0) in component "Y1 4V210-08 manifold"
  line L0 (-65, -16.5) -> (65, -16.5)
  line L1 (65, -16.5) -> (65, 16.5)
  line L2 (65, 16.5) -> (-65, 16.5)
  line L3 (-65, 16.5) -> (-65, -16.5)
extrude "Extrude1'''''''''''''''''''''''''''''''''''''''''''''''''''''''''''''" add sketch "Y1 4V210-08 manifold footprint" along normal blind 16 separate body makes body 86 in component "Y1 4V210-08 manifold"
sketch "Y1 4V210-08 aluminum body footprint" plane through (0, 0, 0) normal (0, 0, 1) x (1, 0, 0) in component "Y1 4V210-08 aluminum body"
  line L0 (-33.5, -11) -> (33.5, -11)
  line L1 (33.5, -11) -> (33.5, 11)
  line L2 (33.5, 11) -> (-33.5, 11)
  line L3 (-33.5, 11) -> (-33.5, -11)
extrude "Extrude1''''''''''''''''''''''''''''''''''''''''''''''''''''''''''''''" add sketch "Y1 4V210-08 aluminum body footprint" along normal blind 24 separate body makes body 87 in component "Y1 4V210-08 aluminum body"
sketch "Y1 spring cap footprint" plane through (0, 0, 0) normal (0, 0, 1) x (1, 0, 0) in component "Y1 spring cap"
  line L0 (-8.5, -11) -> (8.5, -11)
  line L1 (8.5, -11) -> (8.5, 11)
  line L2 (8.5, 11) -> (-8.5, 11)
  line L3 (-8.5, 11) -> (-8.5, -11)
extrude "Extrude1'''''''''''''''''''''''''''''''''''''''''''''''''''''''''''''''" add sketch "Y1 spring cap footprint" along normal blind 24 separate body makes body 88 in component "Y1 spring cap"
sketch "Y1 pilot and manual override footprint" plane through (0, 0, 0) normal (0, 0, 1) x (1, 0, 0) in component "Y1 pilot and manual override"
  line L0 (-11.5, -11) -> (11.5, -11)
  line L1 (11.5, -11) -> (11.5, 11)
  line L2 (11.5, 11) -> (-11.5, 11)
  line L3 (-11.5, 11) -> (-11.5, -11)
extrude "Extrude1''''''''''''''''''''''''''''''''''''''''''''''''''''''''''''''''" add sketch "Y1 pilot and manual override footprint" along normal blind 24 separate body makes body 89 in component "Y1 pilot and manual override"
sketch "Y1 DC24V 4.8W 200mA coil footprint" plane through (0, 0, 0) normal (0, 0, 1) x (1, 0, 0) in component "Y1 DC24V 4.8W 200mA coil"
  line L0 (-20, -12) -> (20, -12)
  line L1 (20, -12) -> (20, 12)
  line L2 (20, 12) -> (-20, 12)
  line L3 (-20, 12) -> (-20, -12)
extrude "Extrude1'''''''''''''''''''''''''''''''''''''''''''''''''''''''''''''''''" add sketch "Y1 DC24V 4.8W 200mA coil footprint" along normal blind 28 separate body makes body 90 in component "Y1 DC24V 4.8W 200mA coil"
sketch "Y1 DIN plug footprint" plane through (0, 0, 0) normal (0, 0, 1) x (1, 0, 0) in component "Y1 DIN plug"
  line L0 (-16, -12) -> (16, -12)
  line L1 (16, -12) -> (16, 12)
  line L2 (16, 12) -> (-16, 12)
  line L3 (-16, 12) -> (-16, -12)
extrude "Extrude1''''''''''''''''''''''''''''''''''''''''''''''''''''''''''''''''''" add sketch "Y1 DIN plug footprint" along normal blind 18 separate body makes body 91 in component "Y1 DIN plug"
sketch "Sketch1 (15)" plane through (0, 0, 0) normal (0, 0, 1) x (1, 0, 0) in component "Y1 manual button"
  circle A0 centre (0, 0) radius 3.5
extrude "Extrude1'''''''''''''''''''''''''''''''''''''''''''''''''''''''''''''''''''" add sketch "Sketch1 (15)" along normal blind 6 separate body makes body 92 in component "Y1 manual button"
sketch "Sketch1 (16)" plane through (0, 0, 0) normal (0, 0, 1) x (1, 0, 0) in component "Y1 port A fitting"
  circle A0 centre (0, 0) radius 6.5
extrude "Extrude1''''''''''''''''''''''''''''''''''''''''''''''''''''''''''''''''''''" add sketch "Sketch1 (16)" along normal blind 11 separate body makes body 93 in component "Y1 port A fitting"
sketch "Sketch1 (17)" plane through (0, 0, 0) normal (0, 0, 1) x (1, 0, 0) in component "Y1 port A collet"
  circle A0 centre (0, 0) radius 4
extrude "Extrude1'''''''''''''''''''''''''''''''''''''''''''''''''''''''''''''''''''''" add sketch "Sketch1 (17)" along normal blind 3 separate body makes body 94 in component "Y1 port A collet"
sketch "Sketch1 (18)" plane through (0, 0, 0) normal (0, 0, 1) x (1, 0, 0) in component "Y1 port B fitting"
  circle A0 centre (0, 0) radius 6.5
extrude "Extrude1''''''''''''''''''''''''''''''''''''''''''''''''''''''''''''''''''''''" add sketch "Sketch1 (18)" along normal blind 11 separate body makes body 95 in component "Y1 port B fitting"
sketch "Sketch1 (19)" plane through (0, 0, 0) normal (0, 0, 1) x (1, 0, 0) in component "Y1 port B collet"
  circle A0 centre (0, 0) radius 4
extrude "Extrude1'''''''''''''''''''''''''''''''''''''''''''''''''''''''''''''''''''''''" add sketch "Sketch1 (19)" along normal blind 3 separate body makes body 96 in component "Y1 port B collet"
sketch "Y2 4V210-08 manifold footprint" plane through (0, 0, 0) normal (0, 0, 1) x (1, 0, 0) in component "Y2 4V210-08 manifold"
  line L0 (-65, -16.5) -> (65, -16.5)
  line L1 (65, -16.5) -> (65, 16.5)
  line L2 (65, 16.5) -> (-65, 16.5)
  line L3 (-65, 16.5) -> (-65, -16.5)
extrude "Extrude1''''''''''''''''''''''''''''''''''''''''''''''''''''''''''''''''''''''''" add sketch "Y2 4V210-08 manifold footprint" along normal blind 16 separate body makes body 97 in component "Y2 4V210-08 manifold"
sketch "Y2 4V210-08 aluminum body footprint" plane through (0, 0, 0) normal (0, 0, 1) x (1, 0, 0) in component "Y2 4V210-08 aluminum body"
  line L0 (-33.5, -11) -> (33.5, -11)
  line L1 (33.5, -11) -> (33.5, 11)
  line L2 (33.5, 11) -> (-33.5, 11)
  line L3 (-33.5, 11) -> (-33.5, -11)
extrude "Extrude1'''''''''''''''''''''''''''''''''''''''''''''''''''''''''''''''''''''''''" add sketch "Y2 4V210-08 aluminum body footprint" along normal blind 24 separate body makes body 98 in component "Y2 4V210-08 aluminum body"
sketch "Y2 spring cap footprint" plane through (0, 0, 0) normal (0, 0, 1) x (1, 0, 0) in component "Y2 spring cap"
  line L0 (-8.5, -11) -> (8.5, -11)
  line L1 (8.5, -11) -> (8.5, 11)
  line L2 (8.5, 11) -> (-8.5, 11)
  line L3 (-8.5, 11) -> (-8.5, -11)
extrude "Extrude1''''''''''''''''''''''''''''''''''''''''''''''''''''''''''''''''''''''''''" add sketch "Y2 spring cap footprint" along normal blind 24 separate body makes body 99 in component "Y2 spring cap"
sketch "Y2 pilot and manual override footprint" plane through (0, 0, 0) normal (0, 0, 1) x (1, 0, 0) in component "Y2 pilot and manual override"
  line L0 (-11.5, -11) -> (11.5, -11)
  line L1 (11.5, -11) -> (11.5, 11)
  line L2 (11.5, 11) -> (-11.5, 11)
  line L3 (-11.5, 11) -> (-11.5, -11)
extrude "Extrude1'''''''''''''''''''''''''''''''''''''''''''''''''''''''''''''''''''''''''''" add sketch "Y2 pilot and manual override footprint" along normal blind 24 separate body makes body 100 in component "Y2 pilot and manual override"
sketch "Y2 DC24V 4.8W 200mA coil footprint" plane through (0, 0, 0) normal (0, 0, 1) x (1, 0, 0) in component "Y2 DC24V 4.8W 200mA coil"
  line L0 (-20, -12) -> (20, -12)
  line L1 (20, -12) -> (20, 12)
  line L2 (20, 12) -> (-20, 12)
  line L3 (-20, 12) -> (-20, -12)
extrude "Extrude1''''''''''''''''''''''''''''''''''''''''''''''''''''''''''''''''''''''''''''" add sketch "Y2 DC24V 4.8W 200mA coil footprint" along normal blind 28 separate body makes body 101 in component "Y2 DC24V 4.8W 200mA coil"
sketch "Y2 DIN plug footprint" plane through (0, 0, 0) normal (0, 0, 1) x (1, 0, 0) in component "Y2 DIN plug"
  line L0 (-16, -12) -> (16, -12)
  line L1 (16, -12) -> (16, 12)
  line L2 (16, 12) -> (-16, 12)
  line L3 (-16, 12) -> (-16, -12)
extrude "Extrude1'''''''''''''''''''''''''''''''''''''''''''''''''''''''''''''''''''''''''''''" add sketch "Y2 DIN plug footprint" along normal blind 18 separate body makes body 102 in component "Y2 DIN plug"
sketch "Sketch1 (20)" plane through (0, 0, 0) normal (0, 0, 1) x (1, 0, 0) in component "Y2 manual button"
  circle A0 centre (0, 0) radius 3.5
extrude "Extrude1''''''''''''''''''''''''''''''''''''''''''''''''''''''''''''''''''''''''''''''" add sketch "Sketch1 (20)" along normal blind 6 separate body makes body 103 in component "Y2 manual button"
sketch "Sketch1 (21)" plane through (0, 0, 0) normal (0, 0, 1) x (1, 0, 0) in component "Y2 port A fitting"
  circle A0 centre (0, 0) radius 6.5
extrude "Extrude1'''''''''''''''''''''''''''''''''''''''''''''''''''''''''''''''''''''''''''''''" add sketch "Sketch1 (21)" along normal blind 11 separate body makes body 104 in component "Y2 port A fitting"
sketch "Sketch1 (22)" plane through (0, 0, 0) normal (0, 0, 1) x (1, 0, 0) in component "Y2 port A collet"
  circle A0 centre (0, 0) radius 4
extrude "Extrude1''''''''''''''''''''''''''''''''''''''''''''''''''''''''''''''''''''''''''''''''" add sketch "Sketch1 (22)" along normal blind 3 separate body makes body 105 in component "Y2 port A collet"
sketch "Sketch1 (23)" plane through (0, 0, 0) normal (0, 0, 1) x (1, 0, 0) in component "Y2 port B fitting"
  circle A0 centre (0, 0) radius 6.5
extrude "Extrude1'''''''''''''''''''''''''''''''''''''''''''''''''''''''''''''''''''''''''''''''''" add sketch "Sketch1 (23)" along normal blind 11 separate body makes body 106 in component "Y2 port B fitting"
sketch "Sketch1 (24)" plane through (0, 0, 0) normal (0, 0, 1) x (1, 0, 0) in component "Y2 port B collet"
  circle A0 centre (0, 0) radius 4
extrude "Extrude1''''''''''''''''''''''''''''''''''''''''''''''''''''''''''''''''''''''''''''''''''" add sketch "Sketch1 (24)" along normal blind 3 separate body makes body 107 in component "Y2 port B collet"
sketch "PLC 1214C envelope footprint" plane through (0, 0, 0) normal (0, 0, 1) x (1, 0, 0) in component "PLC 1214C envelope"
  line L0 (-45, -77.5) -> (45, -77.5)
  line L1 (45, -77.5) -> (45, 77.5)
  line L2 (45, 77.5) -> (-45, 77.5)
  line L3 (-45, 77.5) -> (-45, -77.5)
extrude "Extrude1'''''''''''''''''''''''''''''''''''''''''''''''''''''''''''''''''''''''''''''''''''" add sketch "PLC 1214C envelope footprint" along normal blind 85 separate body makes body 108 in component "PLC 1214C envelope"
sketch "button station envelope footprint" plane through (0, 0, 0) normal (0, 0, 1) x (1, 0, 0) in component "button station envelope"
  line L0 (-37.5, -90) -> (37.5, -90)
  line L1 (37.5, -90) -> (37.5, 90)
  line L2 (37.5, 90) -> (-37.5, 90)
  line L3 (-37.5, 90) -> (-37.5, -90)
extrude "Extrude1''''''''''''''''''''''''''''''''''''''''''''''''''''''''''''''''''''''''''''''''''''" add sketch "button station envelope footprint" along normal blind 35 separate body makes body 109 in component "button station envelope"
sketch "Sketch1 (25)" plane through (0, 0, 0) normal (0, 0, 1) x (1, 0, 0) in component "button EStop"
  circle A0 centre (0, 0) radius 14.5
extrude "Extrude1'''''''''''''''''''''''''''''''''''''''''''''''''''''''''''''''''''''''''''''''''''''" add sketch "Sketch1 (25)" along normal blind 10 separate body makes body 110 in component "button EStop"
sketch "Sketch1 (26)" plane through (0, 0, 0) normal (0, 0, 1) x (1, 0, 0) in component "button Reset"
  circle A0 centre (0, 0) radius 10
extrude "Extrude1''''''''''''''''''''''''''''''''''''''''''''''''''''''''''''''''''''''''''''''''''''''" add sketch "Sketch1 (26)" along normal blind 10 separate body makes body 111 in component "button Reset"
sketch "Sketch1 (27)" plane through (0, 0, 0) normal (0, 0, 1) x (1, 0, 0) in component "button Stop"
  circle A0 centre (0, 0) radius 10
extrude "Extrude1'''''''''''''''''''''''''''''''''''''''''''''''''''''''''''''''''''''''''''''''''''''''" add sketch "Sketch1 (27)" along normal blind 10 separate body makes body 112 in component "button Stop"
sketch "Sketch1 (28)" plane through (0, 0, 0) normal (0, 0, 1) x (1, 0, 0) in component "button Start"
  circle A0 centre (0, 0) radius 10
extrude "Extrude1''''''''''''''''''''''''''''''''''''''''''''''''''''''''''''''''''''''''''''''''''''''''" add sketch "Sketch1 (28)" along normal blind 10 separate body makes body 113 in component "button Start"
component "base board" placed x (1, 0, 0) y (0, 1, 0) z (0, 0, 1) at (0, 0, 0)
component "long conveyor chassis" placed x (1, 0, 0) y (0, 1, 0) z (0, 0, 1) at (-180, -20, 26)
component "long green belt" placed x (1, 0, 0) y (0, 1, 0) z (0, 0, 1) at (-180, -20, 45)
component "front conveyor chassis" placed x (1, 0, 0) y (0, 1, 0) z (0, 0, 1) at (-40, -325, 26)
component "front green belt" placed x (1, 0, 0) y (0, 1, 0) z (0, 0, 1) at (-40, -325, 45)
component "long conveyor side rail -1" placed x (1, 0, 0) y (0, 1, 0) z (0, 0, 1) at (-227, -20, 31)
component "front conveyor side rail -1 left" placed x (1, 0, 0) y (0, 1, 0) z (0, 0, 1) at (-287.5, -369, 31)
component "front conveyor side rail -1 right" placed x (1, 0, 0) y (0, 1, 0) z (0, 0, 1) at (67.5, -369, 31)
component "long conveyor side rail 1" placed x (1, 0, 0) y (0, 1, 0) z (0, 0, 1) at (-133, -20, 31)
component "front conveyor side rail 1 left" placed x (1, 0, 0) y (0, 1, 0) z (0, 0, 1) at (-287.5, -281, 31)
component "front conveyor side rail 1 right" placed x (1, 0, 0) y (0, 1, 0) z (0, 0, 1) at (67.5, -281, 31)
component "front conveyor roller -330" placed x (1, 0, 0) y (0, 0, -1) z (0, 1, 0) at (-330, -362, 29)
component "front conveyor roller 250" placed x (1, 0, 0) y (0, 0, -1) z (0, 1, 0) at (250, -362, 29)
component "long conveyor roller -265" placed x (0, 0, -1) y (0, 1, 0) z (1, 0, 0) at (-219, -265, 29)
component "long conveyor roller 225" placed x (0, 0, -1) y (0, 1, 0) z (1, 0, 0) at (-219, 225, 29)
component "front conveyor DC motor" placed x (1, 0, 0) y (0, 1, 0) z (0, 0, 1) at (285, -325, 24)
component "long conveyor DC motor" placed x (1, 0, 0) y (0, 1, 0) z (0, 0, 1) at (-180, 259, 24)
component "L transfer guide" placed x (1, 0, 0) y (0, 1, 0) z (0, 0, 1) at (-180, -282, 45)
component "gantry post left front" placed x (1, 0, 0) y (0, 1, 0) z (0, 0, 1) at (-305, 10, 12)
component "gantry post left rear" placed x (1, 0, 0) y (0, 1, 0) z (0, 0, 1) at (-305, 425, 12)
component "gantry post right front" placed x (1, 0, 0) y (0, 1, 0) z (0, 0, 1) at (305, 10, 12)
component "gantry post right rear" placed x (1, 0, 0) y (0, 1, 0) z (0, 0, 1) at (305, 425, 12)
component "gantry X rail front" placed x (1, 0, 0) y (0, 1, 0) z (0, 0, 1) at (0, 10, 300)
component "gantry X rail rear" placed x (1, 0, 0) y (0, 1, 0) z (0, 0, 1) at (0, 425, 300)
component "right Y guide" placed x (1, 0, 0) y (0, 1, 0) z (0, 0, 1) at (305, 217, 320)
component "moving Y rail" placed x (1, 0, 0) y (0, 1, 0) z (0, 0, 1) at (-180, 217, 320)
component "pick carriage" placed x (1, 0, 0) y (0, 1, 0) z (0, 0, 1) at (-180, 120, 345)
component "moving Y rail lower guide" placed x (1, 0, 0) y (0, 1, 0) z (0, 0, 1) at (-180, 217, 305)
component "A2 carriage mount" placed x (1, 0, 0) y (0, 1, 0) z (0, 0, 1) at (-180, 120, 290)
component "A2 TN10X75-S twin rod body" placed x (1, 0, 0) y (0, 1, 0) z (0, 0, 1) at (-180, 120, 175)
component "A2 rod at x -191" placed x (1, 0, 0) y (0, 1, 0) z (0, 0, 1) at (-191, 120, 151)
component "A2 rod at x -169" placed x (1, 0, 0) y (0, 1, 0) z (0, 0, 1) at (-169, 120, 151)
component "A2 rod end plate" placed x (1, 0, 0) y (0, 1, 0) z (0, 0, 1) at (-180, 120, 143)